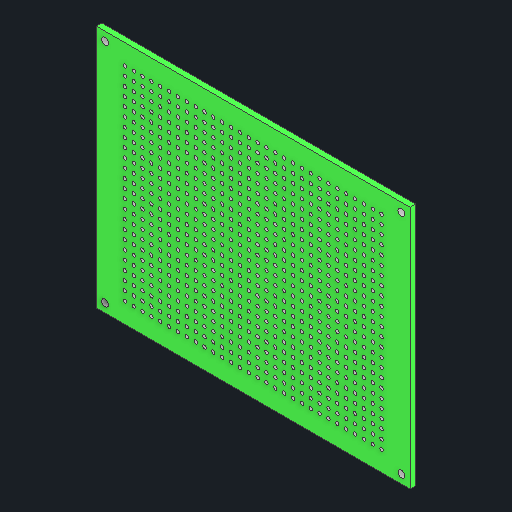
# Autodesk Inventor part: Perfboard 70x90
Saved by Autodesk Inventor 2027.2 (Build 312334000, 334)
## iProperties
Created: 2026-11-06
Part Number: Perfboard 70x90
Material: Generic
Description: Perf board 70 x 90 mm, 2.54 mm grid (24 x 30 holes)
Document SubType Name: Modeling
Designer: isaac
Density: 1 g/cm^3
Appearance: Default
Author: isaac
Autodesk Inventor part; units mm, degrees
ref_plane "YZ Plane" through (0, 0, 0) normal (1, 0, 0) x (0, 1, 0)
ref_plane "XZ Plane" through (0, 0, 0) normal (0, 1, 0) x (-1, 0, 0)
ref_plane "XY Plane" through (0, 0, 0) normal (0, 0, 1) x (1, 0, 0)
sketch "Sketch1" plane through (0, 0, 0) normal (0, 0, 1) x (1, 0, 0)
  line L0 (0, 0) -> (90, 0)
  line L1 (90, 0) -> (90, 70)
  line L2 (90, 70) -> (0, 70)
  line L3 (0, 70) -> (0, 0)
  constraints: 8 end point, 2 parallel, 1 horizontal, 1 perpendicular
extrude "Board" add sketch "Sketch1" along normal blind 1.6
sketch "Sketch2" plane through (0, 0, 0) normal (0, 0, 1) x (1, 0, 0)
  circle A0 centre (8.17, 5.79) radius 0.5
  circle A1 centre (8.17, 8.33) radius 0.5
  circle A2 centre (8.17, 10.87) radius 0.5
  circle A3 centre (8.17, 13.41) radius 0.5
  circle A4 centre (8.17, 15.95) radius 0.5
  circle A5 centre (8.17, 18.49) radius 0.5
  circle A6 centre (8.17, 21.03) radius 0.5
  circle A7 centre (8.17, 23.57) radius 0.5
  circle A8 centre (8.17, 26.11) radius 0.5
  circle A9 centre (8.17, 28.65) radius 0.5
  circle A10 centre (8.17, 31.19) radius 0.5
  circle A11 centre (8.17, 33.73) radius 0.5
  circle A12 centre (8.17, 36.27) radius 0.5
  circle A13 centre (8.17, 38.81) radius 0.5
  circle A14 centre (8.17, 41.35) radius 0.5
  circle A15 centre (8.17, 43.89) radius 0.5
  circle A16 centre (8.17, 46.43) radius 0.5
  circle A17 centre (8.17, 48.97) radius 0.5
  circle A18 centre (8.17, 51.51) radius 0.5
  circle A19 centre (8.17, 54.05) radius 0.5
  circle A20 centre (8.17, 56.59) radius 0.5
  circle A21 centre (8.17, 59.13) radius 0.5
  circle A22 centre (8.17, 61.67) radius 0.5
  circle A23 centre (8.17, 64.21) radius 0.5
  circle A24 centre (10.71, 5.79) radius 0.5
  circle A25 centre (10.71, 8.33) radius 0.5
  circle A26 centre (10.71, 10.87) radius 0.5
  circle A27 centre (10.71, 13.41) radius 0.5
  circle A28 centre (10.71, 15.95) radius 0.5
  circle A29 centre (10.71, 18.49) radius 0.5
  circle A30 centre (10.71, 21.03) radius 0.5
  circle A31 centre (10.71, 23.57) radius 0.5
  circle A32 centre (10.71, 26.11) radius 0.5
  circle A33 centre (10.71, 28.65) radius 0.5
  circle A34 centre (10.71, 31.19) radius 0.5
  circle A35 centre (10.71, 33.73) radius 0.5
  circle A36 centre (10.71, 36.27) radius 0.5
  circle A37 centre (10.71, 38.81) radius 0.5
  circle A38 centre (10.71, 41.35) radius 0.5
  circle A39 centre (10.71, 43.89) radius 0.5
  circle A40 centre (10.71, 46.43) radius 0.5
  circle A41 centre (10.71, 48.97) radius 0.5
  circle A42 centre (10.71, 51.51) radius 0.5
  circle A43 centre (10.71, 54.05) radius 0.5
  circle A44 centre (10.71, 56.59) radius 0.5
  circle A45 centre (10.71, 59.13) radius 0.5
  circle A46 centre (10.71, 61.67) radius 0.5
  circle A47 centre (10.71, 64.21) radius 0.5
  circle A48 centre (13.25, 5.79) radius 0.5
  circle A49 centre (13.25, 8.33) radius 0.5
  circle A50 centre (13.25, 10.87) radius 0.5
  circle A51 centre (13.25, 13.41) radius 0.5
  circle A52 centre (13.25, 15.95) radius 0.5
  circle A53 centre (13.25, 18.49) radius 0.5
  circle A54 centre (13.25, 21.03) radius 0.5
  circle A55 centre (13.25, 23.57) radius 0.5
  circle A56 centre (13.25, 26.11) radius 0.5
  circle A57 centre (13.25, 28.65) radius 0.5
  circle A58 centre (13.25, 31.19) radius 0.5
  circle A59 centre (13.25, 33.73) radius 0.5
  circle A60 centre (13.25, 36.27) radius 0.5
  circle A61 centre (13.25, 38.81) radius 0.5
  circle A62 centre (13.25, 41.35) radius 0.5
  circle A63 centre (13.25, 43.89) radius 0.5
  circle A64 centre (13.25, 46.43) radius 0.5
  circle A65 centre (13.25, 48.97) radius 0.5
  circle A66 centre (13.25, 51.51) radius 0.5
  circle A67 centre (13.25, 54.05) radius 0.5
  circle A68 centre (13.25, 56.59) radius 0.5
  circle A69 centre (13.25, 59.13) radius 0.5
  circle A70 centre (13.25, 61.67) radius 0.5
  circle A71 centre (13.25, 64.21) radius 0.5
  circle A72 centre (15.79, 5.79) radius 0.5
  circle A73 centre (15.79, 8.33) radius 0.5
  circle A74 centre (15.79, 10.87) radius 0.5
  circle A75 centre (15.79, 13.41) radius 0.5
  circle A76 centre (15.79, 15.95) radius 0.5
  circle A77 centre (15.79, 18.49) radius 0.5
  circle A78 centre (15.79, 21.03) radius 0.5
  circle A79 centre (15.79, 23.57) radius 0.5
  circle A80 centre (15.79, 26.11) radius 0.5
  circle A81 centre (15.79, 28.65) radius 0.5
  circle A82 centre (15.79, 31.19) radius 0.5
  circle A83 centre (15.79, 33.73) radius 0.5
  circle A84 centre (15.79, 36.27) radius 0.5
  circle A85 centre (15.79, 38.81) radius 0.5
  circle A86 centre (15.79, 41.35) radius 0.5
  circle A87 centre (15.79, 43.89) radius 0.5
  circle A88 centre (15.79, 46.43) radius 0.5
  circle A89 centre (15.79, 48.97) radius 0.5
  circle A90 centre (15.79, 51.51) radius 0.5
  circle A91 centre (15.79, 54.05) radius 0.5
  circle A92 centre (15.79, 56.59) radius 0.5
  circle A93 centre (15.79, 59.13) radius 0.5
  circle A94 centre (15.79, 61.67) radius 0.5
  circle A95 centre (15.79, 64.21) radius 0.5
  circle A96 centre (18.33, 5.79) radius 0.5
  circle A97 centre (18.33, 8.33) radius 0.5
  circle A98 centre (18.33, 10.87) radius 0.5
  circle A99 centre (18.33, 13.41) radius 0.5
  circle A100 centre (18.33, 15.95) radius 0.5
  circle A101 centre (18.33, 18.49) radius 0.5
  circle A102 centre (18.33, 21.03) radius 0.5
  circle A103 centre (18.33, 23.57) radius 0.5
  circle A104 centre (18.33, 26.11) radius 0.5
  circle A105 centre (18.33, 28.65) radius 0.5
  circle A106 centre (18.33, 31.19) radius 0.5
  circle A107 centre (18.33, 33.73) radius 0.5
  circle A108 centre (18.33, 36.27) radius 0.5
  circle A109 centre (18.33, 38.81) radius 0.5
  circle A110 centre (18.33, 41.35) radius 0.5
  circle A111 centre (18.33, 43.89) radius 0.5
  circle A112 centre (18.33, 46.43) radius 0.5
  circle A113 centre (18.33, 48.97) radius 0.5
  circle A114 centre (18.33, 51.51) radius 0.5
  circle A115 centre (18.33, 54.05) radius 0.5
  circle A116 centre (18.33, 56.59) radius 0.5
  circle A117 centre (18.33, 59.13) radius 0.5
  circle A118 centre (18.33, 61.67) radius 0.5
  circle A119 centre (18.33, 64.21) radius 0.5
  circle A120 centre (20.87, 5.79) radius 0.5
  circle A121 centre (20.87, 8.33) radius 0.5
  circle A122 centre (20.87, 10.87) radius 0.5
  circle A123 centre (20.87, 13.41) radius 0.5
  circle A124 centre (20.87, 15.95) radius 0.5
  circle A125 centre (20.87, 18.49) radius 0.5
  circle A126 centre (20.87, 21.03) radius 0.5
  circle A127 centre (20.87, 23.57) radius 0.5
  circle A128 centre (20.87, 26.11) radius 0.5
  circle A129 centre (20.87, 28.65) radius 0.5
  circle A130 centre (20.87, 31.19) radius 0.5
  circle A131 centre (20.87, 33.73) radius 0.5
  circle A132 centre (20.87, 36.27) radius 0.5
  circle A133 centre (20.87, 38.81) radius 0.5
  circle A134 centre (20.87, 41.35) radius 0.5
  circle A135 centre (20.87, 43.89) radius 0.5
  circle A136 centre (20.87, 46.43) radius 0.5
  circle A137 centre (20.87, 48.97) radius 0.5
  circle A138 centre (20.87, 51.51) radius 0.5
  circle A139 centre (20.87, 54.05) radius 0.5
  circle A140 centre (20.87, 56.59) radius 0.5
  circle A141 centre (20.87, 59.13) radius 0.5
  circle A142 centre (20.87, 61.67) radius 0.5
  circle A143 centre (20.87, 64.21) radius 0.5
  circle A144 centre (23.41, 5.79) radius 0.5
  circle A145 centre (23.41, 8.33) radius 0.5
  circle A146 centre (23.41, 10.87) radius 0.5
  circle A147 centre (23.41, 13.41) radius 0.5
  circle A148 centre (23.41, 15.95) radius 0.5
  circle A149 centre (23.41, 18.49) radius 0.5
  circle A150 centre (23.41, 21.03) radius 0.5
  circle A151 centre (23.41, 23.57) radius 0.5
  circle A152 centre (23.41, 26.11) radius 0.5
  circle A153 centre (23.41, 28.65) radius 0.5
  circle A154 centre (23.41, 31.19) radius 0.5
  circle A155 centre (23.41, 33.73) radius 0.5
  circle A156 centre (23.41, 36.27) radius 0.5
  circle A157 centre (23.41, 38.81) radius 0.5
  circle A158 centre (23.41, 41.35) radius 0.5
  circle A159 centre (23.41, 43.89) radius 0.5
  circle A160 centre (23.41, 46.43) radius 0.5
  circle A161 centre (23.41, 48.97) radius 0.5
  circle A162 centre (23.41, 51.51) radius 0.5
  circle A163 centre (23.41, 54.05) radius 0.5
  circle A164 centre (23.41, 56.59) radius 0.5
  circle A165 centre (23.41, 59.13) radius 0.5
  circle A166 centre (23.41, 61.67) radius 0.5
  circle A167 centre (23.41, 64.21) radius 0.5
  circle A168 centre (25.95, 5.79) radius 0.5
  circle A169 centre (25.95, 8.33) radius 0.5
  circle A170 centre (25.95, 10.87) radius 0.5
  circle A171 centre (25.95, 13.41) radius 0.5
  circle A172 centre (25.95, 15.95) radius 0.5
  circle A173 centre (25.95, 18.49) radius 0.5
  circle A174 centre (25.95, 21.03) radius 0.5
  circle A175 centre (25.95, 23.57) radius 0.5
  circle A176 centre (25.95, 26.11) radius 0.5
  circle A177 centre (25.95, 28.65) radius 0.5
  circle A178 centre (25.95, 31.19) radius 0.5
  circle A179 centre (25.95, 33.73) radius 0.5
  circle A180 centre (25.95, 36.27) radius 0.5
  circle A181 centre (25.95, 38.81) radius 0.5
  circle A182 centre (25.95, 41.35) radius 0.5
  circle A183 centre (25.95, 43.89) radius 0.5
  circle A184 centre (25.95, 46.43) radius 0.5
  circle A185 centre (25.95, 48.97) radius 0.5
  circle A186 centre (25.95, 51.51) radius 0.5
  circle A187 centre (25.95, 54.05) radius 0.5
  circle A188 centre (25.95, 56.59) radius 0.5
  circle A189 centre (25.95, 59.13) radius 0.5
  circle A190 centre (25.95, 61.67) radius 0.5
  circle A191 centre (25.95, 64.21) radius 0.5
  circle A192 centre (28.49, 5.79) radius 0.5
  circle A193 centre (28.49, 8.33) radius 0.5
  circle A194 centre (28.49, 10.87) radius 0.5
  circle A195 centre (28.49, 13.41) radius 0.5
  circle A196 centre (28.49, 15.95) radius 0.5
  circle A197 centre (28.49, 18.49) radius 0.5
  circle A198 centre (28.49, 21.03) radius 0.5
  circle A199 centre (28.49, 23.57) radius 0.5
  circle A200 centre (28.49, 26.11) radius 0.5
  circle A201 centre (28.49, 28.65) radius 0.5
  circle A202 centre (28.49, 31.19) radius 0.5
  circle A203 centre (28.49, 33.73) radius 0.5
  circle A204 centre (28.49, 36.27) radius 0.5
  circle A205 centre (28.49, 38.81) radius 0.5
  circle A206 centre (28.49, 41.35) radius 0.5
  circle A207 centre (28.49, 43.89) radius 0.5
  circle A208 centre (28.49, 46.43) radius 0.5
  circle A209 centre (28.49, 48.97) radius 0.5
  circle A210 centre (28.49, 51.51) radius 0.5
  circle A211 centre (28.49, 54.05) radius 0.5
  circle A212 centre (28.49, 56.59) radius 0.5
  circle A213 centre (28.49, 59.13) radius 0.5
  circle A214 centre (28.49, 61.67) radius 0.5
  circle A215 centre (28.49, 64.21) radius 0.5
  circle A216 centre (31.03, 5.79) radius 0.5
  circle A217 centre (31.03, 8.33) radius 0.5
  circle A218 centre (31.03, 10.87) radius 0.5
  circle A219 centre (31.03, 13.41) radius 0.5
  circle A220 centre (31.03, 15.95) radius 0.5
  circle A221 centre (31.03, 18.49) radius 0.5
  circle A222 centre (31.03, 21.03) radius 0.5
  circle A223 centre (31.03, 23.57) radius 0.5
  circle A224 centre (31.03, 26.11) radius 0.5
  circle A225 centre (31.03, 28.65) radius 0.5
  circle A226 centre (31.03, 31.19) radius 0.5
  circle A227 centre (31.03, 33.73) radius 0.5
  circle A228 centre (31.03, 36.27) radius 0.5
  circle A229 centre (31.03, 38.81) radius 0.5
  circle A230 centre (31.03, 41.35) radius 0.5
  circle A231 centre (31.03, 43.89) radius 0.5
  circle A232 centre (31.03, 46.43) radius 0.5
  circle A233 centre (31.03, 48.97) radius 0.5
  circle A234 centre (31.03, 51.51) radius 0.5
  circle A235 centre (31.03, 54.05) radius 0.5
  circle A236 centre (31.03, 56.59) radius 0.5
  circle A237 centre (31.03, 59.13) radius 0.5
  circle A238 centre (31.03, 61.67) radius 0.5
  circle A239 centre (31.03, 64.21) radius 0.5
  circle A240 centre (33.57, 5.79) radius 0.5
  circle A241 centre (33.57, 8.33) radius 0.5
  circle A242 centre (33.57, 10.87) radius 0.5
  circle A243 centre (33.57, 13.41) radius 0.5
  circle A244 centre (33.57, 15.95) radius 0.5
  circle A245 centre (33.57, 18.49) radius 0.5
  circle A246 centre (33.57, 21.03) radius 0.5
  circle A247 centre (33.57, 23.57) radius 0.5
  circle A248 centre (33.57, 26.11) radius 0.5
  circle A249 centre (33.57, 28.65) radius 0.5
  circle A250 centre (33.57, 31.19) radius 0.5
  circle A251 centre (33.57, 33.73) radius 0.5
  circle A252 centre (33.57, 36.27) radius 0.5
  circle A253 centre (33.57, 38.81) radius 0.5
  circle A254 centre (33.57, 41.35) radius 0.5
  circle A255 centre (33.57, 43.89) radius 0.5
  circle A256 centre (33.57, 46.43) radius 0.5
  circle A257 centre (33.57, 48.97) radius 0.5
  circle A258 centre (33.57, 51.51) radius 0.5
  circle A259 centre (33.57, 54.05) radius 0.5
  circle A260 centre (33.57, 56.59) radius 0.5
  circle A261 centre (33.57, 59.13) radius 0.5
  circle A262 centre (33.57, 61.67) radius 0.5
  circle A263 centre (33.57, 64.21) radius 0.5
  circle A264 centre (36.11, 5.79) radius 0.5
  circle A265 centre (36.11, 8.33) radius 0.5
  circle A266 centre (36.11, 10.87) radius 0.5
  circle A267 centre (36.11, 13.41) radius 0.5
  circle A268 centre (36.11, 15.95) radius 0.5
  circle A269 centre (36.11, 18.49) radius 0.5
  circle A270 centre (36.11, 21.03) radius 0.5
  circle A271 centre (36.11, 23.57) radius 0.5
  circle A272 centre (36.11, 26.11) radius 0.5
  circle A273 centre (36.11, 28.65) radius 0.5
  circle A274 centre (36.11, 31.19) radius 0.5
  circle A275 centre (36.11, 33.73) radius 0.5
  circle A276 centre (36.11, 36.27) radius 0.5
  circle A277 centre (36.11, 38.81) radius 0.5
  circle A278 centre (36.11, 41.35) radius 0.5
  circle A279 centre (36.11, 43.89) radius 0.5
  circle A280 centre (36.11, 46.43) radius 0.5
  circle A281 centre (36.11, 48.97) radius 0.5
  circle A282 centre (36.11, 51.51) radius 0.5
  circle A283 centre (36.11, 54.05) radius 0.5
  circle A284 centre (36.11, 56.59) radius 0.5
  circle A285 centre (36.11, 59.13) radius 0.5
  circle A286 centre (36.11, 61.67) radius 0.5
  circle A287 centre (36.11, 64.21) radius 0.5
  circle A288 centre (38.65, 5.79) radius 0.5
  circle A289 centre (38.65, 8.33) radius 0.5
  circle A290 centre (38.65, 10.87) radius 0.5
  circle A291 centre (38.65, 13.41) radius 0.5
  circle A292 centre (38.65, 15.95) radius 0.5
  circle A293 centre (38.65, 18.49) radius 0.5
  circle A294 centre (38.65, 21.03) radius 0.5
  circle A295 centre (38.65, 23.57) radius 0.5
  circle A296 centre (38.65, 26.11) radius 0.5
  circle A297 centre (38.65, 28.65) radius 0.5
  circle A298 centre (38.65, 31.19) radius 0.5
  circle A299 centre (38.65, 33.73) radius 0.5
  circle A300 centre (38.65, 36.27) radius 0.5
  circle A301 centre (38.65, 38.81) radius 0.5
  circle A302 centre (38.65, 41.35) radius 0.5
  circle A303 centre (38.65, 43.89) radius 0.5
  circle A304 centre (38.65, 46.43) radius 0.5
  circle A305 centre (38.65, 48.97) radius 0.5
  circle A306 centre (38.65, 51.51) radius 0.5
  circle A307 centre (38.65, 54.05) radius 0.5
  circle A308 centre (38.65, 56.59) radius 0.5
  circle A309 centre (38.65, 59.13) radius 0.5
  circle A310 centre (38.65, 61.67) radius 0.5
  circle A311 centre (38.65, 64.21) radius 0.5
  circle A312 centre (41.19, 5.79) radius 0.5
  circle A313 centre (41.19, 8.33) radius 0.5
  circle A314 centre (41.19, 10.87) radius 0.5
  circle A315 centre (41.19, 13.41) radius 0.5
  circle A316 centre (41.19, 15.95) radius 0.5
  circle A317 centre (41.19, 18.49) radius 0.5
  circle A318 centre (41.19, 21.03) radius 0.5
  circle A319 centre (41.19, 23.57) radius 0.5
  circle A320 centre (41.19, 26.11) radius 0.5
  circle A321 centre (41.19, 28.65) radius 0.5
  circle A322 centre (41.19, 31.19) radius 0.5
  circle A323 centre (41.19, 33.73) radius 0.5
  circle A324 centre (41.19, 36.27) radius 0.5
  circle A325 centre (41.19, 38.81) radius 0.5
  circle A326 centre (41.19, 41.35) radius 0.5
  circle A327 centre (41.19, 43.89) radius 0.5
  circle A328 centre (41.19, 46.43) radius 0.5
  circle A329 centre (41.19, 48.97) radius 0.5
  circle A330 centre (41.19, 51.51) radius 0.5
  circle A331 centre (41.19, 54.05) radius 0.5
  circle A332 centre (41.19, 56.59) radius 0.5
  circle A333 centre (41.19, 59.13) radius 0.5
  circle A334 centre (41.19, 61.67) radius 0.5
  circle A335 centre (41.19, 64.21) radius 0.5
  circle A336 centre (43.73, 5.79) radius 0.5
  circle A337 centre (43.73, 8.33) radius 0.5
  circle A338 centre (43.73, 10.87) radius 0.5
  circle A339 centre (43.73, 13.41) radius 0.5
  circle A340 centre (43.73, 15.95) radius 0.5
  circle A341 centre (43.73, 18.49) radius 0.5
  circle A342 centre (43.73, 21.03) radius 0.5
  circle A343 centre (43.73, 23.57) radius 0.5
  circle A344 centre (43.73, 26.11) radius 0.5
  circle A345 centre (43.73, 28.65) radius 0.5
  circle A346 centre (43.73, 31.19) radius 0.5
  circle A347 centre (43.73, 33.73) radius 0.5
  circle A348 centre (43.73, 36.27) radius 0.5
  circle A349 centre (43.73, 38.81) radius 0.5
  circle A350 centre (43.73, 41.35) radius 0.5
  circle A351 centre (43.73, 43.89) radius 0.5
  circle A352 centre (43.73, 46.43) radius 0.5
  circle A353 centre (43.73, 48.97) radius 0.5
  circle A354 centre (43.73, 51.51) radius 0.5
  circle A355 centre (43.73, 54.05) radius 0.5
  circle A356 centre (43.73, 56.59) radius 0.5
  circle A357 centre (43.73, 59.13) radius 0.5
  circle A358 centre (43.73, 61.67) radius 0.5
  circle A359 centre (43.73, 64.21) radius 0.5
  circle A360 centre (46.27, 5.79) radius 0.5
  circle A361 centre (46.27, 8.33) radius 0.5
  circle A362 centre (46.27, 10.87) radius 0.5
  circle A363 centre (46.27, 13.41) radius 0.5
  circle A364 centre (46.27, 15.95) radius 0.5
  circle A365 centre (46.27, 18.49) radius 0.5
  circle A366 centre (46.27, 21.03) radius 0.5
  circle A367 centre (46.27, 23.57) radius 0.5
  circle A368 centre (46.27, 26.11) radius 0.5
  circle A369 centre (46.27, 28.65) radius 0.5
  circle A370 centre (46.27, 31.19) radius 0.5
  circle A371 centre (46.27, 33.73) radius 0.5
  circle A372 centre (46.27, 36.27) radius 0.5
  circle A373 centre (46.27, 38.81) radius 0.5
  circle A374 centre (46.27, 41.35) radius 0.5
  circle A375 centre (46.27, 43.89) radius 0.5
  circle A376 centre (46.27, 46.43) radius 0.5
  circle A377 centre (46.27, 48.97) radius 0.5
  circle A378 centre (46.27, 51.51) radius 0.5
  circle A379 centre (46.27, 54.05) radius 0.5
  circle A380 centre (46.27, 56.59) radius 0.5
  circle A381 centre (46.27, 59.13) radius 0.5
  circle A382 centre (46.27, 61.67) radius 0.5
  circle A383 centre (46.27, 64.21) radius 0.5
  circle A384 centre (48.81, 5.79) radius 0.5
  circle A385 centre (48.81, 8.33) radius 0.5
  circle A386 centre (48.81, 10.87) radius 0.5
  circle A387 centre (48.81, 13.41) radius 0.5
  circle A388 centre (48.81, 15.95) radius 0.5
  circle A389 centre (48.81, 18.49) radius 0.5
  circle A390 centre (48.81, 21.03) radius 0.5
  circle A391 centre (48.81, 23.57) radius 0.5
  circle A392 centre (48.81, 26.11) radius 0.5
  circle A393 centre (48.81, 28.65) radius 0.5
  circle A394 centre (48.81, 31.19) radius 0.5
  circle A395 centre (48.81, 33.73) radius 0.5
  circle A396 centre (48.81, 36.27) radius 0.5
  circle A397 centre (48.81, 38.81) radius 0.5
  circle A398 centre (48.81, 41.35) radius 0.5
  circle A399 centre (48.81, 43.89) radius 0.5
  circle A400 centre (48.81, 46.43) radius 0.5
  circle A401 centre (48.81, 48.97) radius 0.5
  circle A402 centre (48.81, 51.51) radius 0.5
  circle A403 centre (48.81, 54.05) radius 0.5
  circle A404 centre (48.81, 56.59) radius 0.5
  circle A405 centre (48.81, 59.13) radius 0.5
  circle A406 centre (48.81, 61.67) radius 0.5
  circle A407 centre (48.81, 64.21) radius 0.5
  circle A408 centre (51.35, 5.79) radius 0.5
  circle A409 centre (51.35, 8.33) radius 0.5
  circle A410 centre (51.35, 10.87) radius 0.5
  circle A411 centre (51.35, 13.41) radius 0.5
  circle A412 centre (51.35, 15.95) radius 0.5
  circle A413 centre (51.35, 18.49) radius 0.5
  circle A414 centre (51.35, 21.03) radius 0.5
  circle A415 centre (51.35, 23.57) radius 0.5
  circle A416 centre (51.35, 26.11) radius 0.5
  circle A417 centre (51.35, 28.65) radius 0.5
  circle A418 centre (51.35, 31.19) radius 0.5
  circle A419 centre (51.35, 33.73) radius 0.5
  circle A420 centre (51.35, 36.27) radius 0.5
  circle A421 centre (51.35, 38.81) radius 0.5
  circle A422 centre (51.35, 41.35) radius 0.5
  circle A423 centre (51.35, 43.89) radius 0.5
  circle A424 centre (51.35, 46.43) radius 0.5
  circle A425 centre (51.35, 48.97) radius 0.5
  circle A426 centre (51.35, 51.51) radius 0.5
  circle A427 centre (51.35, 54.05) radius 0.5
  circle A428 centre (51.35, 56.59) radius 0.5
  circle A429 centre (51.35, 59.13) radius 0.5
  circle A430 centre (51.35, 61.67) radius 0.5
  circle A431 centre (51.35, 64.21) radius 0.5
  circle A432 centre (53.89, 5.79) radius 0.5
  circle A433 centre (53.89, 8.33) radius 0.5
  circle A434 centre (53.89, 10.87) radius 0.5
  circle A435 centre (53.89, 13.41) radius 0.5
  circle A436 centre (53.89, 15.95) radius 0.5
  circle A437 centre (53.89, 18.49) radius 0.5
  circle A438 centre (53.89, 21.03) radius 0.5
  circle A439 centre (53.89, 23.57) radius 0.5
  circle A440 centre (53.89, 26.11) radius 0.5
  circle A441 centre (53.89, 28.65) radius 0.5
  circle A442 centre (53.89, 31.19) radius 0.5
  circle A443 centre (53.89, 33.73) radius 0.5
  circle A444 centre (53.89, 36.27) radius 0.5
  circle A445 centre (53.89, 38.81) radius 0.5
  circle A446 centre (53.89, 41.35) radius 0.5
  circle A447 centre (53.89, 43.89) radius 0.5
  circle A448 centre (53.89, 46.43) radius 0.5
  circle A449 centre (53.89, 48.97) radius 0.5
  circle A450 centre (53.89, 51.51) radius 0.5
  circle A451 centre (53.89, 54.05) radius 0.5
  circle A452 centre (53.89, 56.59) radius 0.5
  circle A453 centre (53.89, 59.13) radius 0.5
  circle A454 centre (53.89, 61.67) radius 0.5
  circle A455 centre (53.89, 64.21) radius 0.5
  circle A456 centre (56.43, 5.79) radius 0.5
  circle A457 centre (56.43, 8.33) radius 0.5
  circle A458 centre (56.43, 10.87) radius 0.5
  circle A459 centre (56.43, 13.41) radius 0.5
  circle A460 centre (56.43, 15.95) radius 0.5
  circle A461 centre (56.43, 18.49) radius 0.5
  circle A462 centre (56.43, 21.03) radius 0.5
  circle A463 centre (56.43, 23.57) radius 0.5
  circle A464 centre (56.43, 26.11) radius 0.5
  circle A465 centre (56.43, 28.65) radius 0.5
  circle A466 centre (56.43, 31.19) radius 0.5
  circle A467 centre (56.43, 33.73) radius 0.5
  circle A468 centre (56.43, 36.27) radius 0.5
  circle A469 centre (56.43, 38.81) radius 0.5
  circle A470 centre (56.43, 41.35) radius 0.5
  circle A471 centre (56.43, 43.89) radius 0.5
  circle A472 centre (56.43, 46.43) radius 0.5
  circle A473 centre (56.43, 48.97) radius 0.5
  circle A474 centre (56.43, 51.51) radius 0.5
  circle A475 centre (56.43, 54.05) radius 0.5
  circle A476 centre (56.43, 56.59) radius 0.5
  circle A477 centre (56.43, 59.13) radius 0.5
  circle A478 centre (56.43, 61.67) radius 0.5
  circle A479 centre (56.43, 64.21) radius 0.5
  circle A480 centre (58.97, 5.79) radius 0.5
  circle A481 centre (58.97, 8.33) radius 0.5
  circle A482 centre (58.97, 10.87) radius 0.5
  circle A483 centre (58.97, 13.41) radius 0.5
  circle A484 centre (58.97, 15.95) radius 0.5
  circle A485 centre (58.97, 18.49) radius 0.5
  circle A486 centre (58.97, 21.03) radius 0.5
  circle A487 centre (58.97, 23.57) radius 0.5
  circle A488 centre (58.97, 26.11) radius 0.5
  circle A489 centre (58.97, 28.65) radius 0.5
  circle A490 centre (58.97, 31.19) radius 0.5
  circle A491 centre (58.97, 33.73) radius 0.5
  circle A492 centre (58.97, 36.27) radius 0.5
  circle A493 centre (58.97, 38.81) radius 0.5
  circle A494 centre (58.97, 41.35) radius 0.5
  circle A495 centre (58.97, 43.89) radius 0.5
  circle A496 centre (58.97, 46.43) radius 0.5
  circle A497 centre (58.97, 48.97) radius 0.5
  circle A498 centre (58.97, 51.51) radius 0.5
  circle A499 centre (58.97, 54.05) radius 0.5
  circle A500 centre (58.97, 56.59) radius 0.5
  circle A501 centre (58.97, 59.13) radius 0.5
  circle A502 centre (58.97, 61.67) radius 0.5
  circle A503 centre (58.97, 64.21) radius 0.5
  circle A504 centre (61.51, 5.79) radius 0.5
  circle A505 centre (61.51, 8.33) radius 0.5
  circle A506 centre (61.51, 10.87) radius 0.5
  circle A507 centre (61.51, 13.41) radius 0.5
  circle A508 centre (61.51, 15.95) radius 0.5
  circle A509 centre (61.51, 18.49) radius 0.5
  circle A510 centre (61.51, 21.03) radius 0.5
  circle A511 centre (61.51, 23.57) radius 0.5
  circle A512 centre (61.51, 26.11) radius 0.5
  circle A513 centre (61.51, 28.65) radius 0.5
  circle A514 centre (61.51, 31.19) radius 0.5
  circle A515 centre (61.51, 33.73) radius 0.5
  circle A516 centre (61.51, 36.27) radius 0.5
  circle A517 centre (61.51, 38.81) radius 0.5
  circle A518 centre (61.51, 41.35) radius 0.5
  circle A519 centre (61.51, 43.89) radius 0.5
  circle A520 centre (61.51, 46.43) radius 0.5
  circle A521 centre (61.51, 48.97) radius 0.5
  circle A522 centre (61.51, 51.51) radius 0.5
  circle A523 centre (61.51, 54.05) radius 0.5
  circle A524 centre (61.51, 56.59) radius 0.5
  circle A525 centre (61.51, 59.13) radius 0.5
  circle A526 centre (61.51, 61.67) radius 0.5
  circle A527 centre (61.51, 64.21) radius 0.5
  circle A528 centre (64.05, 5.79) radius 0.5
  circle A529 centre (64.05, 8.33) radius 0.5
  circle A530 centre (64.05, 10.87) radius 0.5
  circle A531 centre (64.05, 13.41) radius 0.5
  circle A532 centre (64.05, 15.95) radius 0.5
  circle A533 centre (64.05, 18.49) radius 0.5
  circle A534 centre (64.05, 21.03) radius 0.5
  circle A535 centre (64.05, 23.57) radius 0.5
  circle A536 centre (64.05, 26.11) radius 0.5
  circle A537 centre (64.05, 28.65) radius 0.5
  circle A538 centre (64.05, 31.19) radius 0.5
  circle A539 centre (64.05, 33.73) radius 0.5
  circle A540 centre (64.05, 36.27) radius 0.5
  circle A541 centre (64.05, 38.81) radius 0.5
  circle A542 centre (64.05, 41.35) radius 0.5
  circle A543 centre (64.05, 43.89) radius 0.5
  circle A544 centre (64.05, 46.43) radius 0.5
  circle A545 centre (64.05, 48.97) radius 0.5
  circle A546 centre (64.05, 51.51) radius 0.5
  circle A547 centre (64.05, 54.05) radius 0.5
  circle A548 centre (64.05, 56.59) radius 0.5
  circle A549 centre (64.05, 59.13) radius 0.5
  circle A550 centre (64.05, 61.67) radius 0.5
  circle A551 centre (64.05, 64.21) radius 0.5
  circle A552 centre (66.59, 5.79) radius 0.5
  circle A553 centre (66.59, 8.33) radius 0.5
  circle A554 centre (66.59, 10.87) radius 0.5
  circle A555 centre (66.59, 13.41) radius 0.5
  circle A556 centre (66.59, 15.95) radius 0.5
  circle A557 centre (66.59, 18.49) radius 0.5
  circle A558 centre (66.59, 21.03) radius 0.5
  circle A559 centre (66.59, 23.57) radius 0.5
  circle A560 centre (66.59, 26.11) radius 0.5
  circle A561 centre (66.59, 28.65) radius 0.5
  circle A562 centre (66.59, 31.19) radius 0.5
  circle A563 centre (66.59, 33.73) radius 0.5
  circle A564 centre (66.59, 36.27) radius 0.5
  circle A565 centre (66.59, 38.81) radius 0.5
  circle A566 centre (66.59, 41.35) radius 0.5
  circle A567 centre (66.59, 43.89) radius 0.5
  circle A568 centre (66.59, 46.43) radius 0.5
  circle A569 centre (66.59, 48.97) radius 0.5
  circle A570 centre (66.59, 51.51) radius 0.5
  circle A571 centre (66.59, 54.05) radius 0.5
  circle A572 centre (66.59, 56.59) radius 0.5
  circle A573 centre (66.59, 59.13) radius 0.5
  circle A574 centre (66.59, 61.67) radius 0.5
  circle A575 centre (66.59, 64.21) radius 0.5
  circle A576 centre (69.13, 5.79) radius 0.5
  circle A577 centre (69.13, 8.33) radius 0.5
  circle A578 centre (69.13, 10.87) radius 0.5
  circle A579 centre (69.13, 13.41) radius 0.5
  circle A580 centre (69.13, 15.95) radius 0.5
  circle A581 centre (69.13, 18.49) radius 0.5
  circle A582 centre (69.13, 21.03) radius 0.5
  circle A583 centre (69.13, 23.57) radius 0.5
  circle A584 centre (69.13, 26.11) radius 0.5
  circle A585 centre (69.13, 28.65) radius 0.5
  circle A586 centre (69.13, 31.19) radius 0.5
  circle A587 centre (69.13, 33.73) radius 0.5
  circle A588 centre (69.13, 36.27) radius 0.5
  circle A589 centre (69.13, 38.81) radius 0.5
  circle A590 centre (69.13, 41.35) radius 0.5
  circle A591 centre (69.13, 43.89) radius 0.5
  circle A592 centre (69.13, 46.43) radius 0.5
  circle A593 centre (69.13, 48.97) radius 0.5
  circle A594 centre (69.13, 51.51) radius 0.5
  circle A595 centre (69.13, 54.05) radius 0.5
  circle A596 centre (69.13, 56.59) radius 0.5
  circle A597 centre (69.13, 59.13) radius 0.5
  circle A598 centre (69.13, 61.67) radius 0.5
  circle A599 centre (69.13, 64.21) radius 0.5
  circle A600 centre (71.67, 5.79) radius 0.5
  circle A601 centre (71.67, 8.33) radius 0.5
  circle A602 centre (71.67, 10.87) radius 0.5
  circle A603 centre (71.67, 13.41) radius 0.5
  circle A604 centre (71.67, 15.95) radius 0.5
  circle A605 centre (71.67, 18.49) radius 0.5
  circle A606 centre (71.67, 21.03) radius 0.5
  circle A607 centre (71.67, 23.57) radius 0.5
  circle A608 centre (71.67, 26.11) radius 0.5
  circle A609 centre (71.67, 28.65) radius 0.5
  circle A610 centre (71.67, 31.19) radius 0.5
  circle A611 centre (71.67, 33.73) radius 0.5
  circle A612 centre (71.67, 36.27) radius 0.5
  circle A613 centre (71.67, 38.81) radius 0.5
  circle A614 centre (71.67, 41.35) radius 0.5
  circle A615 centre (71.67, 43.89) radius 0.5
  circle A616 centre (71.67, 46.43) radius 0.5
  circle A617 centre (71.67, 48.97) radius 0.5
  circle A618 centre (71.67, 51.51) radius 0.5
  circle A619 centre (71.67, 54.05) radius 0.5
  circle A620 centre (71.67, 56.59) radius 0.5
  circle A621 centre (71.67, 59.13) radius 0.5
  circle A622 centre (71.67, 61.67) radius 0.5
  circle A623 centre (71.67, 64.21) radius 0.5
  circle A624 centre (74.21, 5.79) radius 0.5
  circle A625 centre (74.21, 8.33) radius 0.5
  circle A626 centre (74.21, 10.87) radius 0.5
  circle A627 centre (74.21, 13.41) radius 0.5
  circle A628 centre (74.21, 15.95) radius 0.5
  circle A629 centre (74.21, 18.49) radius 0.5
  circle A630 centre (74.21, 21.03) radius 0.5
  circle A631 centre (74.21, 23.57) radius 0.5
  circle A632 centre (74.21, 26.11) radius 0.5
  circle A633 centre (74.21, 28.65) radius 0.5
  circle A634 centre (74.21, 31.19) radius 0.5
  circle A635 centre (74.21, 33.73) radius 0.5
  circle A636 centre (74.21, 36.27) radius 0.5
  circle A637 centre (74.21, 38.81) radius 0.5
  circle A638 centre (74.21, 41.35) radius 0.5
  circle A639 centre (74.21, 43.89) radius 0.5
  circle A640 centre (74.21, 46.43) radius 0.5
  circle A641 centre (74.21, 48.97) radius 0.5
  circle A642 centre (74.21, 51.51) radius 0.5
  circle A643 centre (74.21, 54.05) radius 0.5
  circle A644 centre (74.21, 56.59) radius 0.5
  circle A645 centre (74.21, 59.13) radius 0.5
  circle A646 centre (74.21, 61.67) radius 0.5
  circle A647 centre (74.21, 64.21) radius 0.5
  circle A648 centre (76.75, 5.79) radius 0.5
  circle A649 centre (76.75, 8.33) radius 0.5
  circle A650 centre (76.75, 10.87) radius 0.5
  circle A651 centre (76.75, 13.41) radius 0.5
  circle A652 centre (76.75, 15.95) radius 0.5
  circle A653 centre (76.75, 18.49) radius 0.5
  circle A654 centre (76.75, 21.03) radius 0.5
  circle A655 centre (76.75, 23.57) radius 0.5
  circle A656 centre (76.75, 26.11) radius 0.5
  circle A657 centre (76.75, 28.65) radius 0.5
  circle A658 centre (76.75, 31.19) radius 0.5
  circle A659 centre (76.75, 33.73) radius 0.5
  circle A660 centre (76.75, 36.27) radius 0.5
  circle A661 centre (76.75, 38.81) radius 0.5
  circle A662 centre (76.75, 41.35) radius 0.5
  circle A663 centre (76.75, 43.89) radius 0.5
  circle A664 centre (76.75, 46.43) radius 0.5
  circle A665 centre (76.75, 48.97) radius 0.5
  circle A666 centre (76.75, 51.51) radius 0.5
  circle A667 centre (76.75, 54.05) radius 0.5
  circle A668 centre (76.75, 56.59) radius 0.5
  circle A669 centre (76.75, 59.13) radius 0.5
  circle A670 centre (76.75, 61.67) radius 0.5
  circle A671 centre (76.75, 64.21) radius 0.5
  circle A672 centre (79.29, 5.79) radius 0.5
  circle A673 centre (79.29, 8.33) radius 0.5
  circle A674 centre (79.29, 10.87) radius 0.5
  circle A675 centre (79.29, 13.41) radius 0.5
  circle A676 centre (79.29, 15.95) radius 0.5
  circle A677 centre (79.29, 18.49) radius 0.5
  circle A678 centre (79.29, 21.03) radius 0.5
  circle A679 centre (79.29, 23.57) radius 0.5
  circle A680 centre (79.29, 26.11) radius 0.5
  circle A681 centre (79.29, 28.65) radius 0.5
  circle A682 centre (79.29, 31.19) radius 0.5
  circle A683 centre (79.29, 33.73) radius 0.5
  circle A684 centre (79.29, 36.27) radius 0.5
  circle A685 centre (79.29, 38.81) radius 0.5
  circle A686 centre (79.29, 41.35) radius 0.5
  circle A687 centre (79.29, 43.89) radius 0.5
  circle A688 centre (79.29, 46.43) radius 0.5
  circle A689 centre (79.29, 48.97) radius 0.5
  circle A690 centre (79.29, 51.51) radius 0.5
  circle A691 centre (79.29, 54.05) radius 0.5
  circle A692 centre (79.29, 56.59) radius 0.5
  circle A693 centre (79.29, 59.13) radius 0.5
  circle A694 centre (79.29, 61.67) radius 0.5
  circle A695 centre (79.29, 64.21) radius 0.5
  circle A696 centre (81.83, 5.79) radius 0.5
  circle A697 centre (81.83, 8.33) radius 0.5
  circle A698 centre (81.83, 10.87) radius 0.5
  circle A699 centre (81.83, 13.41) radius 0.5
  circle A700 centre (81.83, 15.95) radius 0.5
  circle A701 centre (81.83, 18.49) radius 0.5
  circle A702 centre (81.83, 21.03) radius 0.5
  circle A703 centre (81.83, 23.57) radius 0.5
  circle A704 centre (81.83, 26.11) radius 0.5
  circle A705 centre (81.83, 28.65) radius 0.5
  circle A706 centre (81.83, 31.19) radius 0.5
  circle A707 centre (81.83, 33.73) radius 0.5
  circle A708 centre (81.83, 36.27) radius 0.5
  circle A709 centre (81.83, 38.81) radius 0.5
  circle A710 centre (81.83, 41.35) radius 0.5
  circle A711 centre (81.83, 43.89) radius 0.5
  circle A712 centre (81.83, 46.43) radius 0.5
  circle A713 centre (81.83, 48.97) radius 0.5
  circle A714 centre (81.83, 51.51) radius 0.5
  circle A715 centre (81.83, 54.05) radius 0.5
  circle A716 centre (81.83, 56.59) radius 0.5
  circle A717 centre (81.83, 59.13) radius 0.5
  circle A718 centre (81.83, 61.67) radius 0.5
  circle A719 centre (81.83, 64.21) radius 0.5
  constraints: 720 centre point
extrude "Holes 1.0" cut sketch "Sketch2" along normal through all
sketch "Sketch3" plane through (0, 0, 0) normal (0, 0, 1) x (1, 0, 0)
  circle A0 centre (2.5, 2.5) radius 1
  circle A1 centre (87.5, 2.5) radius 1
  circle A2 centre (2.5, 67.5) radius 1
  circle A3 centre (87.5, 67.5) radius 1
  constraints: 4 centre point
extrude "Mounting holes" cut sketch "Sketch3" along normal through all
body "Solid1"
